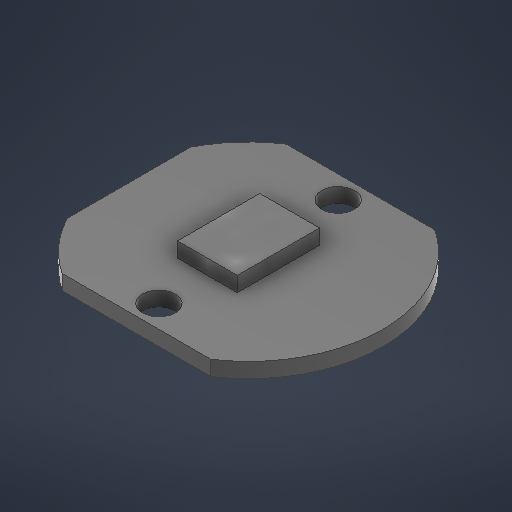
# Autodesk Inventor part: as5048a
Saved by Autodesk Inventor 2027.1 (Build 311270010, 270A)
## iProperties
Created: 2026-10-15
Part Number: as5048a
Material: Generic
Document SubType Name: Modeling
Designer: lucao
Density: 8.22884 g/cm^3
Appearance: Default
Mass: 2 g
Surface Area: 5.29963 cm^2
Volume: 0.243048 cm^3
Author: lucao
Autodesk Inventor part; units mm, degrees
ref_plane "YZ Plane" through (0, 0, 0) normal (1, 0, 0) x (0, 1, 0)
ref_plane "XZ Plane" through (0, 0, 0) normal (0, 1, 0) x (-1, 0, 0)
ref_plane "XY Plane" through (0, 0, 0) normal (0, 0, 1) x (1, 0, 0)
sketch "Sketch2" plane through (0, 0, 0) normal (0, 1, 0) x (-1, 0, 0)
  circle A0 centre (0, 0) radius 9
  line L0 (8, 4.1231) -> (8, -4.1231)
  line L1 (4.9749, 7.5) -> (-4.9749, 7.5)
  line L2 (4.9749, -7.5) -> (-4.9749, -7.5)
  circle A1 centre (0, 6) radius 1.1
  circle A2 centre (0, -6) radius 1.1
  dimension "d8" = 18
  dimension "d9" = 8
  dimension "d10" = 15
  dimension "d11" = 2.2
  dimension "d12" = 2.2
  dimension "d13" = 12
  dimension "d14" = 6
  constraints: 6 end point, 6 point on circle, 3 centre point, 3 vertical alignment, 1 coincident, 1 horizontal, 1 parallel, 1 vertical
  measures "d8" diameter of A0
  measures "d9" distance from line of A0.centre L0
  measures "d10" distance between parallel lines of L1 L2
  measures "d11" diameter of A1
  measures "d12" diameter of A2
  measures "d13" distance of A1.centre A2.centre
  measures "d14" distance of point (0, 0) A1.centre
extrude "Extrusion1" add sketch "Sketch2" along normal blind 1 contours L0 A0 L2 L1
sketch "Sketch3" plane through (0, 1, 0) normal (0, 1, 0) x (1, 0, 0)
  line L0 (2, -2.75) -> (-2, -2.75)
  line L1 (-2, -2.75) -> (-2, 2.75)
  line L2 (-2, 2.75) -> (2, 2.75)
  line L3 (2, 2.75) -> (2, -2.75)
  line L4 (2, -2.75) -> (-2, 2.75) construction
  line L5 (-2, -2.75) -> (2, 2.75) construction
  point P0 (0, 0)
  dimension "d17" = 4
  dimension "d18" = 5.5
  constraints: 12 end point, 2 midpoint, 2 parallel, 1 horizontal, 1 perpendicular
  measures "d17" distance of L1.end L2.end
  measures "d18" distance of L0.end L1.end
extrude "Extrusion2" add sketch "Sketch3" along normal blind 1
body "Solid1"
